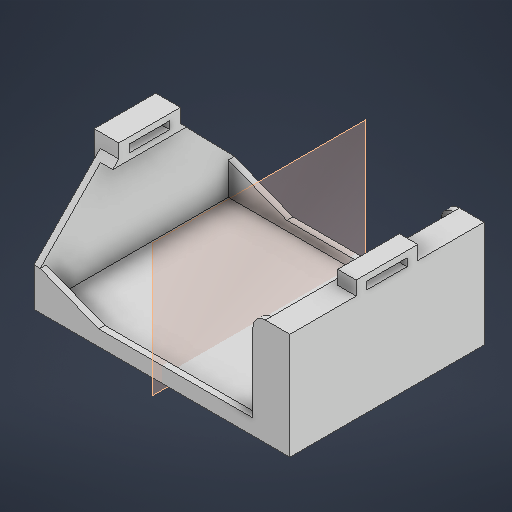
# Autodesk Inventor part: SapFlow Battery Mount_V7
Saved by Autodesk Inventor 2027 (Build 310192060, 192F)
## iProperties
Created: 2026-04-27
Part Number: SapFlow Battery Mount_V7
Material: Generic
Document SubType Name: Modeling
Designer: ngensadmin
Density: 1 g/cm^3
Appearance: Default
Author: ngensadmin
Autodesk Inventor part; units mm, degrees
ref_plane "XZ Plane" through (0, 0, 0) normal (0, 1, 0) x (-1, 0, 0)
ref_plane "XY Plane" through (0, 0, 0) normal (0, 0, 1) x (1, 0, 0)
sketch "Sketch1" plane through (0, 0, 0) normal (0, 1, 0) x (-1, 0, 0)
  line L0 (39.5, 29.5) -> (-39.5, 29.5)
  line L1 (-39.5, 29.5) -> (-39.5, -29.5)
  line L2 (-39.5, -29.5) -> (39.5, -29.5)
  line L3 (39.5, -29.5) -> (39.5, 29.5)
  line L4 (39.5, 29.5) -> (-39.5, -29.5) construction
  line L5 (-39.5, 29.5) -> (39.5, -29.5) construction
  point P0 (0, 0)
  dimension "d0" = 59
  dimension "d1" = 79
  constraints: 12 end point, 2 midpoint, 2 parallel, 1 horizontal, 1 perpendicular
  measures "d0" distance of L2.end L0.start
  measures "d1" distance of L0.start L0.end
extrude "Extrusion1" add sketch "Sketch1" along normal blind 30.5
shell "Shell1" thickness 2 outward yes removed faces 0
sketch "Sketch2" plane through (-41.5, -2, 31.5) normal (0, 0, 1) x (1, 0, 0)
  line L0 (83, 34.5) -> (0, 34.5) projected
  line L1 (71, 34.5) -> (71, 5)
  line L2 (81, 2) -> (2, 2) projected
  line L3 (6, 32.5) -> (6, 34.5)
  line L4 (6, 34.5) -> (71, 34.5)
  line L5 (83, 0) -> (83, 34.5) projected
  line L6 (71, 5) -> (21, 5)
  line L7 (21, 5) -> (2, 12.5)
  line L8 (2, 2) -> (2, 32.5) projected
  line L9 (2, 32.5) -> (6, 32.5)
  line L10 (0, 0) -> (83, 0) projected
  point P0 (41.5, 2)
  point P1 (6, 34.5)
  dimension "d5" = 12
  dimension "d7" = 5
  dimension "d8" = 50
  dimension "d9" = 2
  dimension "d10" = 4
  dimension "d11" = 20
  constraints: 12 end point, 3 point on line, 2 perpendicular, 2 vertical, 1 horizontal, 1 other
  measures "d5" distance between parallel lines of L5 L1
  measures "d7" distance between parallel lines of L10 L6
  measures "d8" distance of L1.end L6.end
  measures "d9" distance between parallel lines of L0 L9
  measures "d10" distance of L9.start L3.start
  measures "d11" distance of L8.end L7.end
extrude "Extrusion2" cut sketch "Sketch2" against normal through all
sketch "Sketch3" plane through (-41.5, -2, -31.5) normal (-1, 0, 0) x (0, 0, 1)
  line L0 (0, 0) -> (63, 0) projected
  line L1 (21.5, 0) -> (41.5, 0)
  line L2 (41.5, 0) -> (41.5, 39)
  line L3 (41.5, 39) -> (21.5, 39)
  line L4 (21.5, 39) -> (21.5, 0)
  line L5 (0, 34.5) -> (63, 34.5) projected
  point P0 (31.5, 0)
  point P1 (41.5, 0)
  dimension "d23" = 20
  dimension "d27" = 4.5
  constraints: 8 end point, 2 midpoint, 2 parallel, 1 horizontal, 1 perpendicular, 1 point on line
  measures "d23" distance of L2.end L3.end
  measures "d27" distance between parallel lines of L5 L3
extrude "Extrusion7" add sketch "Sketch3" along normal blind 2
sketch "Sketch5" plane through (29.5, 3, 31.5) normal (-1, 0, 0) x (0, 0, 1)
  line L0 (-63, 29.5) -> (0, 29.5) projected
  line L1 (-2, 27.5) -> (-61, 27.5) projected
  line L2 (-61, 29.5) -> (-2, 29.5)
  line L3 (-2, 29.5) -> (-2, 27.5)
  line L4 (-2, 27.5) -> (-61, 27.5)
  line L5 (-61, 27.5) -> (-61, 29.5)
  line L6 (-2, 0) -> (-2, 27.5) projected
  line L7 (-61, 27.5) -> (-61, 0) projected
  point P0 (-31.5, -3)
  constraints: 8 end point, 2 collinear, 2 parallel, 2 point on line, 1 horizontal, 1 perpendicular
extrude "Extrusion5" cut sketch "Sketch5" against normal blind 4
fillet "Fillet2" radius 4 2 edges at (29.5, 32.5, -30.5) (29.5, 32.5, 30.5)
sketch "Sketch6" plane through (-41.5, -2, 31.5) normal (-1, 0, 0) x (0, 0, 1)
  line L0 (-21.5, 34.5) -> (0, 34.5) projected
  line L1 (0, 34.5) -> (0, 12.5)
  line L2 (0, 30.5) -> (0, 5) projected
  line L3 (-21.5, 34.5) -> (0, 34.5)
  line L4 (-21.5, 34.5) -> (0, 12.5)
  point P0 (-31.5, 2)
  constraints: 6 end point, 1 perpendicular
extrude "Extrusion8" cut sketch "Sketch6" against normal up to surface (71 mm away)
mirror "Mirror2" about plane through (0, 0, 0) normal (0, 0, 1) of "Extrusion8"
sketch "Sketch7" plane through (0, 32.5, 0) normal (0, 1, 0) x (1, 0, 0)
  line L0 (-41.5, 10) -> (-43.5, 10) projected
  line L1 (-41.5, -10) -> (-35.5, -10) projected
  line L2 (-41.5, 10) -> (-35.5, 10)
  line L3 (-35.5, 10) -> (-35.5, -10)
  line L4 (-35.5, -10) -> (-41.5, -10)
  line L5 (-41.5, -10) -> (-41.5, 10)
  point P0 (0, 0)
  constraints: 8 end point, 2 parallel, 1 horizontal, 1 perpendicular
extrude "Extrusion9" add sketch "Sketch7" along normal up to surface (4.5 mm away)
ref_plane "Work Plane1" through (0, 0, 0) normal (1, 0, 0) x (0, 1, 0)
mirror "Mirror3" about plane through (0, 0, 0) normal (1, 0, 0) of "Extrusion9"
sketch "Sketch10" plane through (-43.5, -2, -31.5) normal (-1, 0, 0) x (0, 0, 1)
  line L0 (2, 34.5) -> (61, 34.5) projected
  line L1 (25, 34.5) -> (38, 34.5)
  line L2 (38, 34.5) -> (38, 37)
  line L3 (38, 37) -> (25, 37)
  line L4 (25, 37) -> (25, 34.5)
  point P0 (31.5, 2)
  point P1 (31.5, 34.5)
  dimension "d34" = 13
  dimension "d35" = 2.5
  constraints: 8 end point, 2 midpoint, 2 parallel, 1 horizontal, 1 perpendicular, 1 point on line
  measures "d34" distance of L2.end L3.end
  measures "d35" distance between parallel lines of L0 L3
extrude "Extrusion10" cut sketch "Sketch10" against normal through all
body "Solid1"
